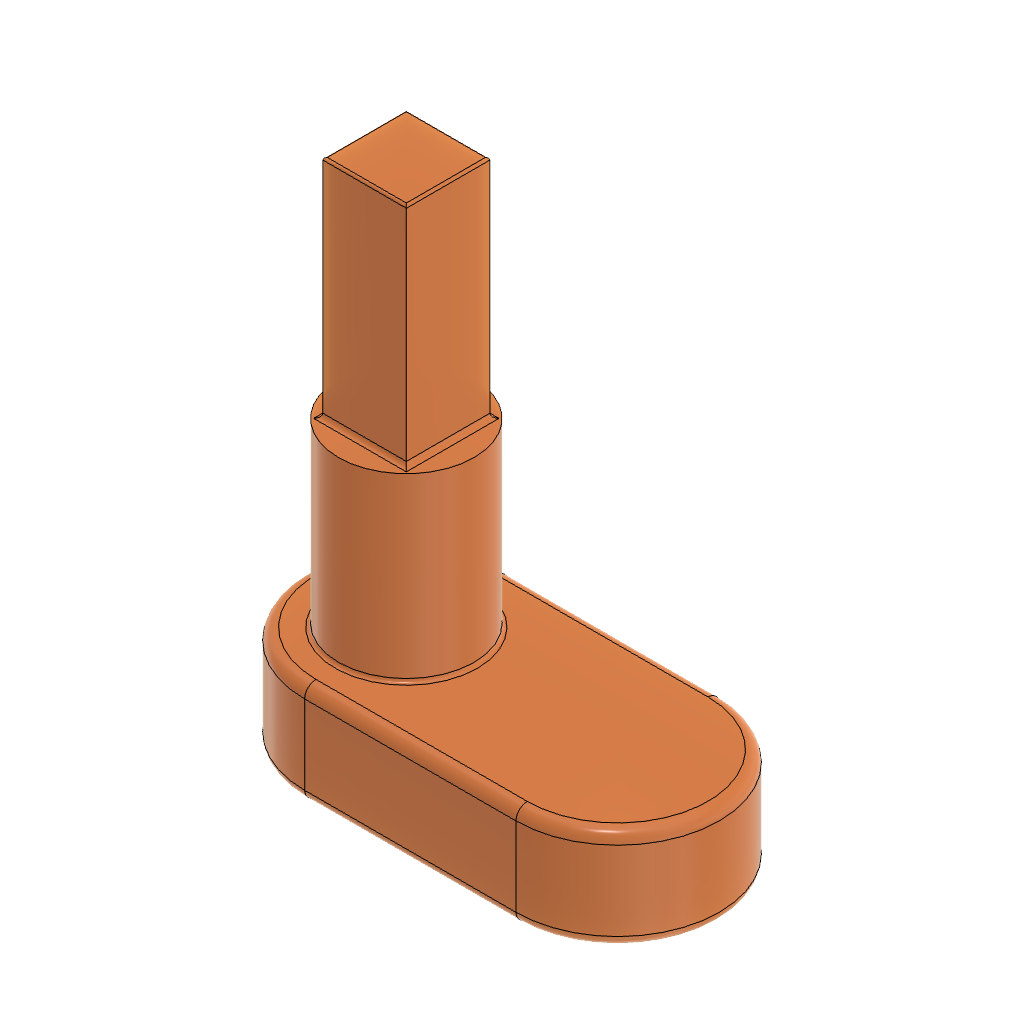
crank_outer_handle_side (Autodesk Fusion 360 design; units mm, degrees)
part number: 2026-10-05-15-22-39-244
Autodesk Fusion 360 part; units mm, degrees
sketch "Sketch1" plane through (0, 0, 0) normal (0, 0, 1) x (1, 0, 0)
  circle A0 centre (-70, 0) radius 9
  circle A1 centre (-70, 0) radius 2.65
  circle A2 centre (-51.3, 0) radius 9
  line L0 (-70, 9) -> (-51.3, 9)
  line L1 (-70, -9) -> (-51.3, -9)
  line L2 (-47.45, -3.85) -> (-55.15, -3.85)
  line L3 (-55.15, -3.85) -> (-55.15, 3.85)
  line L4 (-55.15, 3.85) -> (-47.45, 3.85)
  line L5 (-47.45, 3.85) -> (-47.45, -3.85)
  line L6 (-47.45, -3.85) -> (-55.15, 3.85) construction
  line L7 (-55.15, -3.85) -> (-47.45, 3.85) construction
  point P0 (-51.3, 0)
  dimension "d1" = 18
  dimension "d2" = 5.3
  dimension "d3" = 18
  dimension "d4" = 18.7
  dimension "d5" = 7.7
  dimension "d6" = 7.7
  constraint concentric A0 A1
  constraint coincident A0 L0.start
  constraint coincident A2 L0.end
  constraint tangent A2 L0
  constraint tangent A0 L0
  constraint coincident A0 L1.start
  constraint coincident A2 L1.end
  constraint tangent A2 L1
  constraint tangent A0 L1
  constraint horizontal L2
  constraint perpendicular L2 L3
  constraint parallel L2 L4
  constraint parallel L3 L5
  constraint coincident L6 P0
  constraint coincident L7 P0
  constraint coincident P0 A2.centre
  measures "d1" diameter of A0
  measures "d2" diameter of A1
  measures "d3" diameter of A2
  measures "d4" distance of A0.centre P0
  measures "d5" distance of L3.end L4.end
  measures "d6" distance of L2.end L3.end
extrude "Extrude1" add sketch "Sketch1" along normal blind 9 contours A0 | A0 A2 L0 L1 | A2 | A1
sketch "Sketch2" plane through (0, 0, 9) normal (0, 0, 1) x (-1, 0, 0)
  line L0 (55.15, -3.85) -> (47.45, -3.85)
  line L1 (47.45, -3.85) -> (47.45, 3.85)
  line L2 (47.45, 3.85) -> (55.15, 3.85)
  line L3 (55.15, 3.85) -> (55.15, -3.85)
  arc A0 (70, -9) -> (70, 9) centre (70, 0) ccw
  line L4 (70, 9) -> (51.3, 9)
  arc A1 (51.3, 9) -> (51.3, -9) centre (51.3, 0) ccw
  line L5 (51.3, -9) -> (70, -9)
  line L6 (55.15, -3.85) -> (47.45, -3.85)
  line L7 (47.45, -3.85) -> (47.45, 3.85)
  line L8 (47.45, 3.85) -> (55.15, 3.85)
  line L9 (55.15, 3.85) -> (55.15, -3.85)
  constraint horizontal L6
  constraint vertical L7
  constraint horizontal L8
  constraint vertical L9
  constraint coincident L1.end L2.start
  constraint coincident L0.start L3.end
extrude "Extrude2" add sketch "Sketch2" against normal blind 2 contours L0 L1 L2 L3 L6 L7 L8 L9
sketch "Sketch3" plane through (0, 0, 9) normal (0, 0, 1) x (-1, 0, 0)
  arc A0 (70, -9) -> (70, 9) centre (70, 0) ccw
  line L0 (70, 9) -> (51.3, 9)
  arc A1 (51.3, 9) -> (51.3, -9) centre (51.3, 0) ccw
  line L1 (51.3, -9) -> (70, -9)
  circle A2 centre (70, 0) radius 6
  dimension "d11" = 12
  constraint concentric A0 A2
  measures "d11" diameter of A2
extrude "Extrude3" add sketch "Sketch3" along normal blind 16 contours A2
sketch "Sketch4" plane through (0, 0, 25) normal (0, 0, 1) x (-1, 0, 0)
  circle A0 centre (70, 0) radius 6
  line L0 (66.3, -3.7) -> (73.7, -3.7)
  line L1 (73.7, -3.7) -> (73.7, 3.7)
  line L2 (73.7, 3.7) -> (66.3, 3.7)
  line L3 (66.3, 3.7) -> (66.3, -3.7)
  line L4 (66.3, -3.7) -> (73.7, 3.7) construction
  line L5 (73.7, -3.7) -> (66.3, 3.7) construction
  point P0 (70, 0)
  dimension "d14" = 7.4
  dimension "d15" = 7.4
  constraint horizontal L0
  constraint perpendicular L0 L1
  constraint parallel L0 L2
  constraint parallel L1 L3
  constraint coincident L4 P0
  constraint coincident L5 P0
  constraint coincident P0 A0.centre
  measures "d14" distance of L1.end L2.end
  measures "d15" distance of L0.end L1.end
extrude "Extrude4" add sketch "Sketch4" along normal blind 20 contours L0 L1 L2 L3
fillet "Fillet1" radius 1 4 edges at (-42.3, 0, 9) (-60.65, 9, 9) (-79, 0, 9) (-60.65, -9, 9)
fillet "Fillet2" radius 1 4 edges at (-60.65, 9, 0) (-79, 0, 0) (-60.65, -9, 0) (-42.3, 0, 0)
fillet "Fillet3" radius 0.4 4 edges at (-66.3, 0, 25) (-70, -3.7, 25) (-70, 3.7, 25) (-73.7, 0, 25)
fillet "Fillet4" radius 0.3 1 edges at (-64.406, -2.1697, 9)
fillet "Fillet5" radius 0.2 4 edges at (-70, -3.7, 45) (-73.7, 0, 45) (-66.3, 0, 45) (-70, 3.7, 45)
